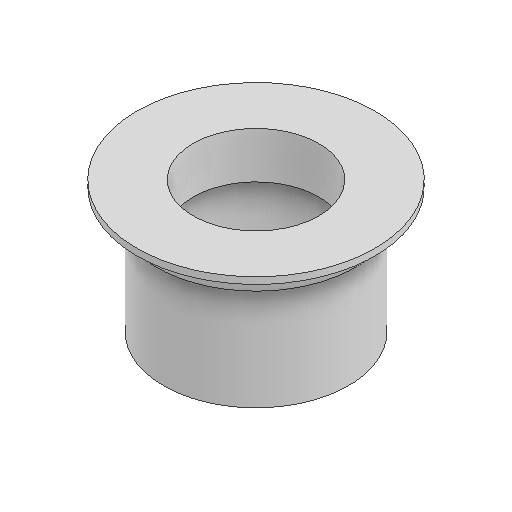
# Autodesk Inventor part: 3DP_PLA_HTD3M_6mm_Belt_Idler
Saved by Autodesk Inventor 2027 (Build 310192060, 192F)
## iProperties
Created: 2026-01-06
Part Number: 3DP_PLA_HTD3M_6mm_Belt_Idler
Material: Generic
Document SubType Name: Modeling
Designer: User
Density: 1 g/cm^3
Appearance: Default
Author: User
Autodesk Inventor part; units mm, degrees
ref_plane "YZ Plane" through (0, 0, 0) normal (1, 0, 0) x (0, 1, 0)
ref_plane "XZ Plane" through (0, 0, 0) normal (0, 1, 0) x (-1, 0, 0)
ref_plane "XY Plane" through (0, 0, 0) normal (0, 0, 1) x (1, 0, 0)
sketch "Sketch2" plane through (0, 0, 0) normal (0, 1, 0) x (-1, 0, 0)
  circle A0 centre (0, 0) radius 6
  circle A1 centre (0, 0) radius 4.75
  circle A2 centre (0, 0) radius 7
  circle A3 centre (0, 0) radius 9
  dimension "d0" = 12
  dimension "d1" = 9.5
  dimension "d2" = 1
  dimension "d3" = 2
  constraints: 4 centre point, 2 coincident
  measures "d0" diameter of A0
  measures "d1" diameter of A1
  measures "d2" radial gap between concentric circles of A0 A2
  measures "d3" radial gap between concentric circles of A2 A3
extrude "Extrusion1" add sketch "Sketch2" along normal blind 2 contours A0 | A2 | A3
extrude "Extrusion2" add sketch "Sketch2" against normal blind 8 contours A2
chamfer "Chamfer1" distance 1.5 angle 45 1 edges at (9, 0, 0)
sketch "Sketch3" plane through (0, 0, 0) normal (0, -1, 0) x (1, 0, 0)
  circle A0 centre (0, 0) radius 6 projected
  circle A1 centre (0, 0) radius 4.75 projected
extrude "Extrusion3" add sketch "Sketch3" along normal blind 1.5
body "Solid1"
